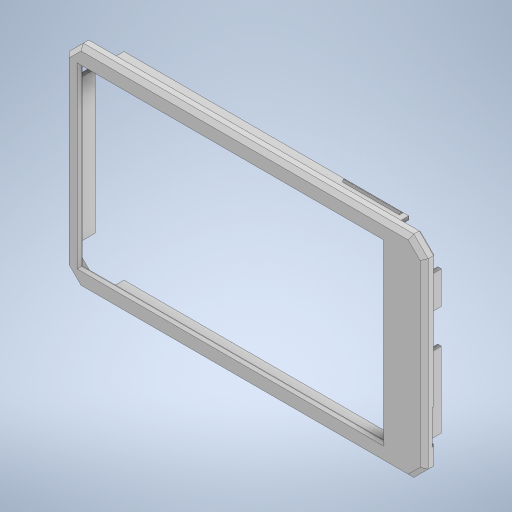
# Autodesk Inventor part: Pièce2
Saved by Autodesk Inventor 2024 (Build 280153000, 153)
## iProperties
Created: 2026-10-29
Part Number: Pièce2
Material: Générique
Document SubType Name: Modeling
Designer: berno
Density: 1 g/cm^3
Appearance: Par défaut
Author: berno
Autodesk Inventor part; units mm, degrees
sketch "Esquisse1" plane through (0, 0, 0) normal (0, 0, 1) x (1, 0, 0)
  line L0 (63, 37) -> (-63, 37)
  line L1 (-63, 37) -> (-63, -37)
  line L2 (-63, -37) -> (63, -37)
  line L3 (63, -37) -> (63, 37)
  line L4 (61.5, 35.5) -> (-61.5, 35.5)
  line L5 (-61.5, 35.5) -> (-61.5, -35.5)
  line L6 (-61.5, -35.5) -> (61.5, -35.5)
  line L7 (61.5, -35.5) -> (61.5, 35.5)
  point P0 (0, 0)
  point P1 (63, 0)
  point P2 (0, -37)
  point P3 (0, -35.5)
  point P4 (61.5, 0)
  dimension "d0" = 0
  dimension "d1" = 0
  dimension "d2" = 0
  dimension "d3" = 0
  dimension "d4" = 74
  dimension "d5" = 71
  dimension "d6" = 126
  dimension "d7" = 123
  constraints: 16 end point, 4 midpoint, 4 parallel, 2 horizontal, 2 perpendicular
  measures "d0" vertical distance of point (0, 0) point (63, 0)
  measures "d1" horizontal distance of point (0, 0) point (0, -37)
  measures "d2" horizontal distance of point (0, 0) point (0, -35.5)
  measures "d3" vertical distance of point (0, 0) point (61.5, 0)
  measures "d4" distance of L2.end L0.start
  measures "d5" distance of L6.end L4.start
  measures "d6" distance of L1.end L2.end
  measures "d7" distance of L5.end L6.end
extrude "Extrusion1" add sketch "Esquisse1" along normal blind 3
chamfer "Chanfrein1" distance 5 angle 45 8 edges at (-63, 37, 1.5) (-61.5, 35.5, 1.5) (-63, -37, 1.5) (-61.5, -35.5, 1.5) (61.5, -35.5, 1.5) (63, -37, 1.5) (63, 37, 1.5) (61.5, 35.5, 1.5)
sketch "Esquisse2" plane through (0, 0, 3) normal (0, 0, 1) x (1, 0, 0)
  line L0 (58, 37) -> (-58, 37) projected
  line L1 (63, 32) -> (58, 37) projected
  line L2 (58, 37) -> (63, 32)
  line L3 (63, -32) -> (63, 32) projected
  line L4 (63, 32) -> (63, -32)
  line L5 (63, -32) -> (58, -37)
  line L6 (-63, -32) -> (-58, -37) projected
  line L7 (58, -37) -> (-58, -37)
  line L8 (-58, -37) -> (-63, -32)
  line L9 (-63, 32) -> (-63, -32) projected
  line L10 (-63, -32) -> (-63, 32)
  line L11 (-63, 32) -> (-58, 37)
  line L12 (-58, 37) -> (58, 37)
  line L13 (48, 30.5) -> (-58, 30.5)
  line L14 (-58, 30.5) -> (-58, -30.5)
  line L15 (-58, -30.5) -> (48, -30.5)
  line L16 (48, -30.5) -> (48, 30.5)
  point P0 (0, 0)
  point P1 (48, 0)
  point P2 (-5, -30.5)
  dimension "d13" = 0
  dimension "d15" = 61
  dimension "d17" = 5
  dimension "d18" = 15
  constraints: 24 end point, 5 equal length, 5 perpendicular, 2 midpoint, 2 point on line, 1 horizontal
  measures "d13" vertical distance of point (0, 0) point (48, 0)
  measures "d15" distance of L15.end L13.start
  measures "d17" distance between parallel lines of L14 L9
  measures "d18" distance between parallel lines of L3 L16
extrude "Extrusion2" add sketch "Esquisse2" along normal blind 1
chamfer "Chanfrein2" distance 1.4 angle 45 16 edges at (-60.5, 34.5, 4) (-63, 0, 4) (-60.5, -34.5, 4) (0, -37, 4) (60.5, -34.5, 4) (63, 0, 4) (0, 37, 4) (60.5, 34.5, 4) (-59, 33, 3) (-61.5, 0, 3) (-59, -33, 3) (0, -35.5, 3) (59, -33, 3) (61.5, 0, 3) (59, 33, 3) (0, 35.5, 3)
sketch "Esquisse3" plane through (0, 0, 0) normal (0, 0, -1) x (-1, 0, 0)
  line L0 (-63, -32) -> (-63, 32) projected
  line L1 (-63, 32) -> (-58, 37) projected
  line L2 (-63, 32) -> (-58, 37)
  line L3 (58, 37) -> (63, 32) projected
  line L4 (-58, 37) -> (58, 37)
  line L5 (58, 37) -> (63, 32)
  line L6 (63, 32) -> (63, -32)
  line L7 (63, -32) -> (58, -37)
  line L8 (58, -37) -> (-58, -37)
  line L9 (-58, -37) -> (-63, -32)
  line L10 (-63, -32) -> (-63, 32)
  line L11 (-61.6, 31.4201) -> (-61.6, -31.4201) projected
  line L12 (58, 37) -> (56.5, 35.5)
  line L13 (63, 32) -> (63, -32) projected
  line L14 (61.5, 30.5) -> (63, 32)
  line L15 (61.5, -30.5) -> (63, -32)
  line L16 (56.5, -35.5) -> (61.5, -30.5) projected
  line L17 (56.5, -35.5) -> (58, -37)
  line L18 (-61.6, -31.4201) -> (-63, -32) projected
  line L19 (-61.5, -30.5) -> (-63, -32)
  line L20 (-61.5, -30.5) -> (-56.5, -35.5) projected
  line L21 (-56.5, -35.5) -> (-58, -37)
  line L22 (-56.5, 35.5) -> (-61.5, 30.5) projected
  line L23 (-56.5, 35.5) -> (-58, 37)
  line L24 (-61.5, 30.5) -> (-63, 32)
  line L25 (57.7, 36.7) -> (62.7, 31.7)
  line L26 (62.7, 31.7) -> (62.7, -31.7)
  line L27 (62.7, -31.7) -> (57.7, -36.7)
  line L28 (57.7, -36.7) -> (-57.7, -36.7)
  line L29 (-57.7, -36.7) -> (-62.7, -31.7)
  line L30 (-62.7, -31.7) -> (-62.7, 31.7)
  line L31 (-62.7, 31.7) -> (-57.7, 36.7)
  line L32 (-57.7, 36.7) -> (57.7, 36.7)
  line L33 (-55.9201, 34.1) -> (55.9201, 34.1) projected
  line L34 (63, 32) -> (63, -32) projected
  line L35 (-58, 37) -> (58, 37) projected
  line L36 (-58, -37) -> (-63, -32) projected
  dimension "d82" = 0.3
  constraints: 48 end point, 12 perpendicular, 9 point on line, 8 parallel, 2 collinear, 1 horizontal, 1 vertical
  measures "d82" distance between parallel lines of L35 L32
extrude "Extrusion3" [suppressed]
sketch "Esquisse4" plane through (-56.5, -35.5, 0) normal (0, 1, 0) x (1, 0, 0)
  line L0 (113, -1.6) -> (0, -1.6) projected
  line L1 (0, 0) -> (-5, 0) projected
  line L2 (113, -1.6) -> (0, -1.6)
  line L3 (0, -1.6) -> (0, 0)
  line L4 (0, 0) -> (113, 0)
  line L5 (113, 0) -> (113, -1.6)
  line L6 (89.25, -1.6) -> (83.75, -1.6)
  line L7 (83.75, -1.6) -> (83.75, 0)
  line L8 (83.75, 0) -> (89.25, 0)
  line L9 (89.25, 0) -> (89.25, -1.6)
  line L10 (115.9, 0) -> (-0.9, 0) projected
  line L11 (23.75, 0) -> (29.25, 0)
  line L12 (29.25, 0) -> (29.25, -1.6)
  line L13 (29.25, -1.6) -> (23.75, -1.6)
  line L14 (23.75, -1.6) -> (23.75, 0)
  line L15 (113, 0) -> (0, 0) projected
  point P0 (56.5, 0)
  point P1 (86.5, -1.6)
  point P2 (56.5, 0)
  point P3 (26.5, -1.6)
  point P4 (57.5, 0)
  point P5 (23.75, -0.8)
  point P6 (83.75, -0.8)
  point P7 (89.25, -0.8)
  point P8 (23.75, 0)
  point P9 (23.75, -1.6)
  point P10 (29.25, -1.6)
  point P11 (29.25, 0)
  point P12 (89.25, -1.6)
  point P13 (89.25, 0)
  point P14 (83.75, -1.6)
  point P15 (56.5, 0)
  dimension "d28" = 30
  dimension "d30" = 5.5
  dimension "d31" = 5.5
  dimension "d96" = 30
  constraints: 24 end point, 6 midpoint, 6 parallel, 3 horizontal, 3 perpendicular, 3 point on line, 5 other
  measures "d28" horizontal distance of point (86.5, -1.6) point (56.5, 0)
  measures "d30" distance from line of point (23.75, -0.8) L12
  measures "d31" distance of point (83.75, -0.8) point (89.25, -0.8)
  measures "d96" horizontal distance of point (26.5, -1.6) point (56.5, 0)
extrude "Extrusion4" [suppressed]
sketch "Esquisse5" plane through (-56.5, -34, 0) normal (0, 1, 0) x (1, 0, 0)
  line L0 (83.75, -1.6) -> (89.25, -1.6) projected
  line L1 (89.25, 0) -> (83.75, 0) projected
  line L2 (89.25, -1.6) -> (83.75, -1.6)
  line L3 (83.75, -1.6) -> (83.75, 0)
  line L4 (83.75, 0) -> (89.25, 0)
  line L5 (89.25, 0) -> (89.25, -1.6)
  line L6 (23.75, -1.6) -> (29.25, -1.6) projected
  line L7 (29.25, 0) -> (23.75, 0) projected
  line L8 (29.25, -1.6) -> (23.75, -1.6)
  line L9 (23.75, -1.6) -> (23.75, 0)
  line L10 (23.75, 0) -> (29.25, 0)
  line L11 (29.25, 0) -> (29.25, -1.6)
  line L12 (89.25, -1.6) -> (83.75, -1.6)
  line L13 (83.75, -1.6) -> (83.75, 2.6)
  line L14 (83.75, 2.6) -> (89.25, 2.6)
  line L15 (89.25, 2.6) -> (89.25, -1.6)
  line L16 (29.25, -1.6) -> (23.75, -1.6)
  line L17 (23.75, -1.6) -> (23.75, 2.6)
  line L18 (23.75, 2.6) -> (29.25, 2.6)
  line L19 (29.25, 2.6) -> (29.25, -1.6)
  line L20 (89.25, 2.6) -> (83.75, 2.6)
  line L21 (83.75, 2.6) -> (83.75, 4.4)
  line L22 (83.75, 4.4) -> (89.25, 4.4)
  line L23 (89.25, 4.4) -> (89.25, 2.6)
  line L24 (29.25, 2.6) -> (23.75, 2.6)
  line L25 (23.75, 2.6) -> (23.75, 4.4)
  line L26 (23.75, 4.4) -> (29.25, 4.4)
  line L27 (29.25, 4.4) -> (29.25, 2.6)
  point P0 (56.5, 0)
  point P1 (86.5, -1.6)
  point P2 (86.5, 2.6)
  point P3 (26.5, -1.6)
  point P4 (23.75, 3.5)
  point P5 (29.25, 3.5)
  point P6 (83.75, 3.5)
  point P7 (89.25, 3.5)
  point P8 (23.75, 0)
  point P9 (23.75, -1.6)
  point P10 (23.75, 0)
  dimension "d34" = 4.2
  dimension "d35" = 5.5
  dimension "d36" = 5.5
  dimension "d37" = 4.2
  dimension "d38" = 5.5
  dimension "d39" = 1.8
  dimension "d40" = 1.8
  dimension "d41" = 5.5
  constraints: 48 end point, 12 parallel, 7 midpoint, 6 horizontal, 6 perpendicular
  measures "d34" distance of point (86.5, -1.6) point (86.5, 2.6)
  measures "d35" distance between parallel lines of L13 L15
  measures "d36" distance between parallel lines of L17 L19
  measures "d37" distance from line of point (26.5, -1.6) L18
  measures "d38" distance of point (23.75, 3.5) point (29.25, 3.5)
  measures "d39" distance between parallel lines of L18 L26
  measures "d40" distance between parallel lines of L14 L22
  measures "d41" distance of point (83.75, 3.5) point (89.25, 3.5)
extrude "Extrusion5" [suppressed]
sketch "Esquisse6" plane through (-56.5, -35, 0) normal (0, -1, 0) x (1, 0, 0)
  line L0 (83.75, -4.4) -> (89.25, -4.4) projected
  line L1 (89.25, 1.6) -> (89.25, -4.4) projected
  line L2 (83.75, -4.4) -> (89.25, -4.4)
  line L3 (89.25, -4.4) -> (89.25, -2.6)
  line L4 (89.25, -2.6) -> (83.75, -2.6)
  line L5 (83.75, -2.6) -> (83.75, -4.4)
  line L6 (29.25, -4.4) -> (23.75, -4.4) projected
  line L7 (23.75, -4.4) -> (29.25, -4.4)
  line L8 (29.25, -4.4) -> (29.25, -2.6)
  line L9 (29.25, -2.6) -> (23.75, -2.6)
  line L10 (23.75, -2.6) -> (23.75, -4.4)
  point P0 (56.5, 0)
  point P1 (26.5, -2.6)
  point P2 (26.5, -4.4)
  point P3 (29.25, -3.5)
  point P4 (23.75, -3.5)
  dimension "d44" = 1.8
  dimension "d45" = 5.5
  constraints: 16 end point, 4 midpoint, 4 parallel, 2 horizontal, 2 perpendicular, 2 point on line
  measures "d44" distance of point (26.5, -2.6) point (26.5, -4.4)
  measures "d45" distance of point (29.25, -3.5) point (23.75, -3.5)
extrude "Extrusion6" [suppressed]
sketch "Esquisse7" plane through (-56.5, 35.5, 0) normal (0, -1, 0) x (1, 0, 0)
  line L0 (0, 0) -> (113, 0) projected
  line L1 (0, 1.6) -> (113, 1.6) projected
  line L2 (83.75, 0) -> (89.25, 0)
  line L3 (89.25, 0) -> (89.25, 1.6)
  line L4 (89.25, 1.6) -> (83.75, 1.6)
  line L5 (83.75, 1.6) -> (83.75, 0)
  line L6 (29.25, 0) -> (23.75, 0)
  line L7 (23.75, 0) -> (23.75, 1.6)
  line L8 (23.75, 1.6) -> (29.25, 1.6)
  line L9 (29.25, 1.6) -> (29.25, 0)
  point P0 (56.5, 0)
  point P1 (56.5, 0)
  point P2 (26.5, 0)
  point P3 (86.5, 0)
  point P4 (56.5, 0)
  point P5 (83.75, 0.8)
  point P6 (29.25, 0.8)
  point P7 (23.75, 0.8)
  point P8 (83.75, 1.6)
  point P9 (89.25, 0)
  point P10 (29.25, 0)
  point P11 (29.25, 1.6)
  point P12 (23.75, 1.6)
  dimension "d55" = 30
  dimension "d56" = 30
  dimension "d57" = 5.5
  dimension "d58" = 5.5
  constraints: 16 end point, 7 midpoint, 4 parallel, 4 point on line, 2 horizontal, 2 perpendicular
  measures "d55" distance of point (56.5, 0) point (26.5, 0)
  measures "d56" distance of point (86.5, 0) point (56.5, 0)
  measures "d57" horizontal distance of L3.end point (83.75, 0.8)
  measures "d58" distance of point (29.25, 0.8) point (23.75, 0.8)
extrude "Extrusion7" [suppressed]
sketch "Esquisse8" plane through (-56.5, 34, 0) normal (0, -1, 0) x (1, 0, 0)
  line L0 (23.75, 1.6) -> (23.75, 0) projected
  line L1 (23.75, 1.6) -> (29.25, 1.6)
  line L2 (29.25, 1.6) -> (29.25, -4.4)
  line L3 (29.25, -4.4) -> (23.75, -4.4)
  line L4 (23.75, -4.4) -> (23.75, 1.6)
  line L5 (89.25, 1.6) -> (83.75, 1.6) projected
  line L6 (83.75, 1.6) -> (89.25, 1.6)
  line L7 (89.25, 1.6) -> (89.25, -4.4)
  line L8 (89.25, -4.4) -> (83.75, -4.4)
  line L9 (83.75, -4.4) -> (83.75, 1.6)
  point P0 (56.5, 0)
  point P1 (83.75, -1.4)
  point P2 (89.25, -1.4)
  dimension "d61" = 6
  dimension "d62" = 5.5
  dimension "d63" = 6
  dimension "d64" = 5.5
  constraints: 16 end point, 4 parallel, 2 horizontal, 2 midpoint, 2 perpendicular
  measures "d61" distance between parallel lines of L1 L3
  measures "d62" distance between parallel lines of L2 L4
  measures "d63" distance between parallel lines of L5 L8
  measures "d64" distance of point (83.75, -1.4) point (89.25, -1.4)
extrude "Extrusion8" [suppressed]
sketch "Esquisse9" plane through (-56.5, 35, 0) normal (0, 1, 0) x (1, 0, 0)
  line L0 (29.25, 4.4) -> (23.75, 4.4)
  line L1 (23.75, 4.4) -> (23.75, 2.6)
  line L2 (23.75, 2.6) -> (29.25, 2.6)
  line L3 (29.25, 2.6) -> (29.25, 4.4)
  line L4 (29.25, 4.4) -> (23.75, 4.4) projected
  line L5 (29.25, 4.4) -> (23.75, 4.4) projected
  line L6 (23.75, 4.4) -> (23.75, 0) projected
  line L7 (89.25, 4.4) -> (89.25, -1.6) projected
  line L8 (83.75, -1.6) -> (83.75, 4.4) projected
  line L9 (89.25, 0) -> (89.25, 4.4) projected
  line L10 (89.25, 4.4) -> (83.75, 4.4)
  line L11 (83.75, 4.4) -> (83.75, 2.6)
  line L12 (83.75, 2.6) -> (89.25, 2.6)
  line L13 (89.25, 2.6) -> (89.25, 4.4)
  point P0 (56.5, 0)
  point P1 (26.5, 4.4)
  point P2 (23.75, 3.5)
  point P3 (83.75, 1.5)
  dimension "d69" = 5.5
  dimension "d80" = 0
  dimension "d83" = 0
  dimension "d103" = 1.8
  dimension "d104" = 1.8
  constraints: 16 end point, 4 parallel, 2 horizontal, 2 midpoint, 2 perpendicular, 2 point on line
  measures "d69" distance between parallel lines of L3 L1
  measures "d80" distance between parallel lines of L5 L0
  measures "d83" distance between parallel lines of L1 L6
  measures "d103" distance between parallel lines of L0 L2
  measures "d104" distance between parallel lines of L12 L10
extrude "Extrusion9" [suppressed]
chamfer "Chanfrein7" [suppressed]
chamfer "Chanfrein9" [suppressed]
chamfer "Chanfrein10" [suppressed]
chamfer "Chanfrein11" [suppressed]
fillet "Congé3" [suppressed]
sketch "Esq Languette" plane through (0, 0, 0) normal (0, 0, 1) x (1, 0, 0)
  line L0 (-50, 34.15) -> (50, 34.15)
  line L1 (50, 34.15) -> (50, 35.35)
  line L2 (50, 35.35) -> (-50, 35.35)
  line L3 (-50, 35.35) -> (-50, 34.15)
  line L4 (-50, -35.35) -> (50, -35.35)
  line L5 (50, -35.35) -> (50, -34.15)
  line L6 (50, -34.15) -> (-50, -34.15)
  line L7 (-50, -34.15) -> (-50, -35.35)
  line L8 (-61.35, -25) -> (-60.15, -25)
  line L9 (-60.15, -25) -> (-60.15, 25)
  line L10 (-60.15, 25) -> (-61.35, 25)
  line L11 (-61.35, 25) -> (-61.35, -25)
  line L12 (60.15, -25) -> (61.35, -25)
  line L13 (61.35, -25) -> (61.35, 1.5)
  line L14 (61.35, 1.5) -> (60.15, 1.5)
  line L15 (60.15, 1.5) -> (60.15, -25)
  line L16 (60.15, 13.5) -> (61.35, 13.5)
  line L17 (61.35, 13.5) -> (61.35, 25)
  line L18 (61.35, 25) -> (60.15, 25)
  line L19 (60.15, 25) -> (60.15, 13.5)
  constraints: 40 end point, 10 parallel, 5 horizontal, 5 perpendicular
extrude "Languette" add sketch "Esq Languette" against normal blind 4
chamfer "Chanfrein languette" distance 0.35 angle 45 20 edges at (0, -35.35, -4) (-50, -34.75, -4) (0, -34.15, -4) (50, -34.75, -4) (-60.75, -25, -4) (-61.35, 0, -4) (-60.75, 25, -4) (-60.15, 0, -4) (60.75, 13.5, -4) (60.15, 19.25, -4) (60.75, 25, -4) (61.35, 19.25, -4) (60.75, -25, -4) (60.15, -11.75, -4) (60.75, 1.5, -4) (61.35, -11.75, -4) (0, 34.15, -4) (-50, 34.75, -4) (0, 35.35, -4) (50, 34.75, -4)
ref_plane "Plan de construction1" through (30, 0, 0) normal (1, 0, 0) x (0, 1, 0)
sketch "Esq Bosses X+" plane through (30, 0, 0) normal (1, 0, 0) x (0, 1, 0)
  line L0 (35, -3.5) -> (35.35, -3.5)
  line L1 (35.35, -3.5) -> (35.85, -2.6)
  line L2 (35.85, -2.6) -> (35.35, -2.1)
  line L3 (35.35, -2.1) -> (35, -2.1)
  line L4 (35, -2.1) -> (35, -3.5)
  line L5 (-35, -3.5) -> (-35.35, -3.5)
  line L6 (-35.35, -3.5) -> (-35.85, -2.6)
  line L7 (-35.85, -2.6) -> (-35.35, -2.1)
  line L8 (-35.35, -2.1) -> (-35, -2.1)
  line L9 (-35, -2.1) -> (-35, -3.5)
  constraints: 20 end point
extrude "Bosses X+" [suppressed]
ref_plane "Plan de construction2" through (-30, 0, 0) normal (1, 0, 0) x (0, 1, 0)
sketch "Esq Bosses X-" plane through (-30, 0, 0) normal (1, 0, 0) x (0, 1, 0)
  line L0 (35, -3.5) -> (35.35, -3.5)
  line L1 (35.35, -3.5) -> (35.85, -2.6)
  line L2 (35.85, -2.6) -> (35.35, -2.1)
  line L3 (35.35, -2.1) -> (35, -2.1)
  line L4 (35, -2.1) -> (35, -3.5)
  line L5 (-35, -3.5) -> (-35.35, -3.5)
  line L6 (-35.35, -3.5) -> (-35.85, -2.6)
  line L7 (-35.85, -2.6) -> (-35.35, -2.1)
  line L8 (-35.35, -2.1) -> (-35, -2.1)
  line L9 (-35, -2.1) -> (-35, -3.5)
  constraints: 20 end point
extrude "Bosses X-" [suppressed]
sketch "Esq Liaison languette" plane through (0, 0, 0) normal (0, 0, 1) x (1, 0, 0)
  line L0 (-50, 34.15) -> (50, 34.15)
  line L1 (50, 34.15) -> (50, 36)
  line L2 (50, 36) -> (-50, 36)
  line L3 (-50, 36) -> (-50, 34.15)
  line L4 (-50, -36) -> (50, -36)
  line L5 (50, -36) -> (50, -34.15)
  line L6 (50, -34.15) -> (-50, -34.15)
  line L7 (-50, -34.15) -> (-50, -36)
  line L8 (-62, -25) -> (-60.15, -25)
  line L9 (-60.15, -25) -> (-60.15, 25)
  line L10 (-60.15, 25) -> (-62, 25)
  line L11 (-62, 25) -> (-62, -25)
  line L12 (60.15, -25) -> (62, -25)
  line L13 (62, -25) -> (62, 1.5)
  line L14 (62, 1.5) -> (60.15, 1.5)
  line L15 (60.15, 1.5) -> (60.15, -25)
  line L16 (60.15, 13.5) -> (62, 13.5)
  line L17 (62, 13.5) -> (62, 25)
  line L18 (62, 25) -> (60.15, 25)
  line L19 (60.15, 25) -> (60.15, 13.5)
  constraints: 40 end point, 10 parallel, 5 horizontal, 5 perpendicular
extrude "Liaison languette" add sketch "Esq Liaison languette" along normal blind 1.6
ref_plane "Plan de construction3" through (0, 14.5, 0) normal (0, 1, 0) x (-1, 0, 0)
sketch "Esq Patte haut Y+" plane through (0, 14.5, 0) normal (0, 1, 0) x (-1, 0, 0)
  line L0 (61, -2.5) -> (62.25, -2.5)
  line L1 (62.25, -2.5) -> (62.25, -1.9)
  line L2 (62.25, -1.9) -> (61.85, -1.5)
  line L3 (61.85, -1.5) -> (61, -1.5)
  line L4 (61, -1.5) -> (61, -2.5)
  constraints: 10 end point
extrude "Patte haut Y+" add sketch "Esq Patte haut Y+" along normal mid plane 15
ref_plane "Plan de construction4" through (0, -14.5, 0) normal (0, 1, 0) x (-1, 0, 0)
sketch "Esq Patte haut Y-" plane through (0, -14.5, 0) normal (0, 1, 0) x (-1, 0, 0)
  line L0 (61, -2.5) -> (62.25, -2.5)
  line L1 (62.25, -2.5) -> (62.25, -1.9)
  line L2 (62.25, -1.9) -> (61.85, -1.5)
  line L3 (61.85, -1.5) -> (61, -1.5)
  line L4 (61, -1.5) -> (61, -2.5)
  constraints: 10 end point
extrude "Patte haut Y-" add sketch "Esq Patte haut Y-" along normal mid plane 15
ref_plane "Plan de construction5" through (38, 0, 0) normal (1, 0, 0) x (0, 1, 0)
sketch "Esq Crochets bas" plane through (38, 0, 0) normal (1, 0, 0) x (0, 1, 0)
  line L0 (35, -3.6) -> (35.35, -3.6)
  line L1 (35.35, -3.6) -> (36, -2.7)
  line L2 (36, -2.7) -> (35.35, -2.325)
  line L3 (35.35, -2.325) -> (35, -2.325)
  line L4 (35, -2.325) -> (35, -3.6)
  line L5 (-35, -3.6) -> (-35.35, -3.6)
  line L6 (-35.35, -3.6) -> (-36, -2.7)
  line L7 (-36, -2.7) -> (-35.35, -2.325)
  line L8 (-35.35, -2.325) -> (-35, -2.325)
  line L9 (-35, -2.325) -> (-35, -3.6)
  constraints: 20 end point
extrude "Crochets bas" add sketch "Esq Crochets bas" along normal mid plane 20
sketch "Esq Ligne d'ombre" plane through (0, 0, 0) normal (0, 0, 1) x (1, 0, 0)
  line L0 (-66, -40) -> (66, -40)
  line L1 (66, -40) -> (66, 40)
  line L2 (66, 40) -> (-66, 40)
  line L3 (-66, 40) -> (-66, -40)
  line L4 (62.3, 31.71) -> (57.71, 36.3)
  line L5 (57.71, 36.3) -> (-57.71, 36.3)
  line L6 (-57.71, 36.3) -> (-62.3, 31.71)
  line L7 (-62.3, 31.71) -> (-62.3, -31.71)
  line L8 (-62.3, -31.71) -> (-57.71, -36.3)
  line L9 (-57.71, -36.3) -> (57.71, -36.3)
  line L10 (57.71, -36.3) -> (62.3, -31.71)
  line L11 (62.3, -31.71) -> (62.3, 31.71)
  constraints: 24 end point, 2 parallel, 1 horizontal, 1 perpendicular
extrude "Ligne d'ombre" cut sketch "Esq Ligne d'ombre" along normal blind 0.7
sketch "Esq Encoche ongle" plane through (0, 0, 0) normal (0, 0, 1) x (1, 0, 0)
  line L0 (61.6, -26) -> (64, -26)
  line L1 (64, -26) -> (64, -14)
  line L2 (64, -14) -> (61.6, -14)
  line L3 (61.6, -14) -> (61.6, -26)
  constraints: 8 end point, 2 parallel, 1 horizontal, 1 perpendicular
extrude "Encoche ongle" cut sketch "Esq Encoche ongle" along normal blind 1.2
chamfer "Chanfrein fenetre" distance 0.8 angle 45 4 edges at (48, 0, 4) (-5, -30.5, 4) (-58, 0, 4) (-5, 30.5, 4)
